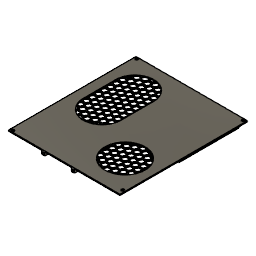
top-cover (Autodesk Fusion 360 design; units mm, degrees)
Autodesk Fusion 360 part; units mm, degrees
sketch "Sketch1" plane through (0, 0, 0) normal (0, 0, 1) x (1, 0, 0)
  line L0 (111, -154) -> (-111, -154)
  line L1 (-111, 100) -> (111, 100)
  circle A0 centre (106, -143.5) radius 1.95
  line L2 (-109, -154) -> (-103, -154)
  line L3 (-103, 100) -> (-109, 100)
  line L4 (109, -140) -> (103, -140)
  line L5 (-111, 100) -> (-111, -154)
  line L6 (-109, -147) -> (-109, 93)
  line L7 (111, 100) -> (111, -154)
  line L8 (-103, 93) -> (-103, 100)
  circle A1 centre (-106, -150.5) radius 1.95
  line L9 (103, 100) -> (103, 93)
  line L10 (-103, -147) -> (-109, -147)
  line L11 (-111, -154) -> (-109, -154)
  line L12 (103, -154) -> (111, -154)
  line L13 (-109, -154) -> (-109, -147)
  line L14 (111, 100) -> (103, 100)
  line L15 (-109, 93) -> (-103, 93)
  circle A2 centre (106, -143.5) radius 1.95
  circle A3 centre (-106, -150.5) radius 1.95
  circle A4 centre (106, 96.5) radius 1.95
  line L16 (103, -140) -> (103, -154)
  line L17 (-109, 100) -> (-109, 93)
  line L18 (-109, 100) -> (-111, 100)
  circle A5 centre (-106, 96.5) radius 1.95
  line L19 (103, 93) -> (109, 93)
  line L20 (111, -154) -> (111, 100)
  line L21 (-111, -154) -> (-111, 100)
  line L22 (109, 93) -> (109, -140)
  circle A6 centre (-106, 96.5) radius 1.95
  circle A7 centre (106, 96.5) radius 1.95
  line L23 (-103, -154) -> (-103, -147)
  line L24 (-109, -147) -> (-109, -154)
  line L25 (-109, 93) -> (-109, 100)
  circle A8 centre (-106, 96.5) radius 2.725
  circle A9 centre (106, 96.5) radius 2.725
  circle A10 centre (106, -143.5) radius 2.725
  circle A11 centre (-106, -150.5) radius 2.725
  line L26 (-109, 84.9738) -> (-107, 84.9738)
  line L27 (-107, 84.9738) -> (-107, -35.0262)
  line L28 (-107, -35.0262) -> (-109, -35.0262)
  line L29 (-109, -35.0262) -> (-109, 84.9738)
  line L30 (109, 84.9738) -> (107, 84.9738)
  line L31 (107, 84.9738) -> (107, -35.0262)
  line L32 (107, -35.0262) -> (109, -35.0262)
  line L33 (109, -35.0262) -> (109, 84.9738)
  point P0 (0, 100)
  dimension "d3" = 5.45
  dimension "d4" = 5.45
  dimension "d5" = 5.45
  dimension "d6" = 5.45
  dimension "d11" = 2
  dimension "d12" = 120
  dimension "d13" = 222
  dimension "d14" = 254
  dimension "d15" = 2
  dimension "d16" = 120
  constraint horizontal L1
  constraint vertical L7
  constraint horizontal L0
  constraint vertical L21
  constraint coincident L0.start L7.end
  constraint coincident L1.start L5.start
  constraint concentric A1 A3
  constraint concentric A4 A7
  constraint concentric A6 A8
  constraint concentric A7 A9
  constraint concentric A2 A10
  constraint concentric A1 A11
  constraint horizontal L26
  constraint vertical L27
  constraint horizontal L28
  constraint vertical L29
  constraint coincident L6 L26.start
  constraint vertical L20
  constraint vertical L22
  constraint vertical L6
  constraint vertical L16
  constraint horizontal L4
  constraint horizontal L10
  constraint vertical L23
  constraint horizontal L19
  constraint vertical L9
  constraint horizontal L15
  constraint vertical L8
  constraint horizontal L30
  constraint vertical L31
  constraint horizontal L32
  constraint vertical L33
  constraint coincident L22 L30.start
  constraint collinear L26 L30
  measures "d3" diameter of A8
  measures "d4" diameter of A9
  measures "d5" diameter of A10
  measures "d6" diameter of A11
  measures "d11" distance of L26.start L26.end
  measures "d12" distance of L26.start L28.end
  measures "d13" distance of L1.end L1.start
  measures "d14" distance of L1.end L0.start
  measures "d15" distance of L30.start L30.end
  measures "d16" distance of L30.start L32.end
extrude "Extrude1" add sketch "Sketch1" along normal blind 2 contours L0 L1 L4 L7 L9 L12 L14 L16 L19 L20 L22 L33 | L0 L1 L4 L6 L8 L9 L10 L15 L16 L19 L22 L23 L26 L27 L28 L30 L31 L32 | L0 L2 L10 L13 L23 L24 | L0 L1 L5 L6 L11 L13 L17 L18 L21 L24 L25 L29 | L1 L3 L8 L15 L17 L25 | L22 L30 L31 L32 L33 | L6 L26 L27 L28 L29 makes body 1
extrude "Extrude2" add sketch "Sketch1" along normal blind 1 contours A8 | A9 | A10 | A11 bodies 1
extrude "Extrude3" add sketch "Sketch1" against normal blind 4 contours L22 L30 L31 L32 L33 | L6 L26 L27 L28 L29 bodies 1
sketch "Sketch2" plane through (0, -154, 0) normal (0, -1, 0) x (1, 0, 0)
  line L0 (-111, 0) -> (111, 0)
  line L1 (111, 0) -> (111, 2)
  line L2 (111, 2) -> (-111, 2)
  line L3 (-111, 2) -> (-111, 0)
  line L4 (-111, 2) -> (-86, 2)
  line L5 (-86, 2) -> (-86, 0)
  line L6 (-86, 0) -> (-111, 0)
  line L7 (-111, 0) -> (-111, 2)
  line L8 (111, 2) -> (86, 2)
  line L9 (86, 2) -> (86, 0)
  line L10 (86, 0) -> (111, 0)
  line L11 (111, 0) -> (111, 2)
  line L12 (-86, 2) -> (86, 2)
  line L13 (86, 2) -> (86, 0)
  line L14 (86, 0) -> (-86, 0)
  line L15 (-86, 0) -> (-86, 2)
  dimension "d19" = 25
  dimension "d20" = 25
  constraint horizontal L4
  constraint vertical L5
  constraint horizontal L6
  constraint vertical L7
  constraint coincident L2.end L3.start
  constraint horizontal L8
  constraint vertical L9
  constraint horizontal L10
  constraint vertical L11
  constraint coincident L1.end L2.start
  constraint horizontal L12
  constraint vertical L13
  constraint horizontal L14
  constraint vertical L15
  measures "d19" distance of L2.end L4.end
  measures "d20" distance of L1.end L8.end
fillet "Fillet3" radius 0.5 4 edges at (104.182, -142.7948, 1) (104.182, 97.2052, 1) (-107.818, 97.2052, 1) (-107.818, -149.7949, 1) on bodies 1
sketch "Sketch3" plane through (0, 0, 0) normal (0, 0, -1) x (1, 0, 0)
  line L0 (109, -84.9738) -> (107, -84.9738)
  line L1 (107, -84.9738) -> (107, 35.0262)
  line L2 (107, 35.0262) -> (109, 35.0262)
  line L3 (109, 35.0262) -> (109, -84.9738)
  line L4 (-107, 35.0262) -> (-107, -84.9738)
  line L5 (-107, -84.9738) -> (-109, -84.9738)
  line L6 (-109, -84.9738) -> (-109, 35.0262)
  line L7 (-109, 35.0262) -> (-107, 35.0262)
  circle A0 centre (-106, 150.5) radius 1.95
  circle A1 centre (-106, -96.5) radius 1.95
  circle A2 centre (106, 143.5) radius 1.95
  circle A3 centre (106, -96.5) radius 1.95
  line L8 (111, 154) -> (-111, 154)
  line L9 (-111, 154) -> (-111, -100)
  line L10 (-111, -100) -> (111, -100)
  line L11 (111, -100) -> (111, 154)
  line L12 (-111, 154) -> (-44.9, 154)
  line L13 (-44.9, 154) -> (-38.9, 154)
  line L14 (-38.9, 154) -> (-38.9, 145)
  line L15 (-38.9, 145) -> (-44.9, 145)
  line L16 (-44.9, 145) -> (-44.9, 154)
  line L17 (14.1, 154) -> (20.1, 154)
  line L18 (20.1, 154) -> (20.1, 145)
  line L19 (20.1, 145) -> (14.1, 145)
  line L20 (14.1, 145) -> (14.1, 154)
  dimension "d27" = 66.1
  dimension "d29" = 6
  dimension "d30" = 9
  dimension "d33" = 6
  dimension "d34" = 9
  dimension "d35" = 53
  constraint coincident L8.end L9.start
  constraint perpendicular L9 L12
  constraint horizontal L13
  constraint vertical L14
  constraint horizontal L15
  constraint vertical L16
  constraint horizontal L17
  constraint vertical L18
  constraint horizontal L19
  constraint vertical L20
  constraint collinear L13 L17
  constraint coincident L12.end L13.start
  measures "d27" distance of L8.end L12.end
  measures "d29" distance of L12.end L13.end
  measures "d30" distance of L12.end L15.end
  measures "d33" distance of L17.start L17.end
  measures "d34" distance of L17.start L19.end
  measures "d35" distance of L14 L20
extrude "Extrude5" add sketch "Sketch3" along normal blind 7 contours L8 L17 L18 L19 L20 | L8 L13 L14 L15 L16 bodies 1
sketch "Sketch4" plane through (0, -154, 0) normal (0, -1, 0) x (1, 0, 0)
  line L0 (-111, 0) -> (-44.9, 0)
  line L1 (-44.9, 0) -> (-44.9, -7)
  line L2 (-44.9, -7) -> (-38.9, -7)
  line L3 (-38.9, -7) -> (-38.9, 0)
  circle A0 centre (-41.9, -4) radius 1.95
  circle A1 centre (17.1, -4) radius 1.95
  line L4 (14.1, 0) -> (14.1, -7)
  line L5 (20.1, -7) -> (14.1, -7)
  line L6 (-38.9, 0) -> (14.1, 0)
  line L7 (14.1, 0) -> (14.1, -7)
  line L8 (14.1, -7) -> (20.1, -7)
  line L9 (20.1, -7) -> (20.1, 0)
  line L10 (20.1, 0) -> (111, 0)
  line L11 (111, 0) -> (111, 2)
  line L12 (111, 2) -> (-111, 2)
  line L13 (-111, 2) -> (-111, 0)
  line L14 (-38.9, 0) -> (-44.9, 0)
  line L15 (20.1, 0) -> (14.1, 0)
  dimension "d36" = 3.9
  dimension "d37" = 3.9
  dimension "d43" = 3
  dimension "d44" = 3
  dimension "d47" = 4
  dimension "d48" = 4
  measures "d36" diameter of A0
  measures "d37" diameter of A1
  measures "d43" distance of A1.centre L4
  measures "d44" distance of L1 A0.centre
  measures "d47" distance of A0.centre L14
  measures "d48" distance of A1.centre L15
extrude "Extrude6" cut sketch "Sketch4" against normal blind 8 contours A0 | A1 bodies 1
fillet "Fillet4" radius 0.4 2 edges at (-43.718, -154, -3.2948) (15.282, -154, -3.2948) on bodies 1
sketch "Sketch5" plane through (0, 0, 2) normal (0, 0, 1) x (-1, 0, 0)
  line L0 (111, 154) -> (-111, 154)
  line L1 (-111, 154) -> (-111, -100)
  line L2 (-111, -100) -> (111, -100)
  line L3 (111, -100) -> (111, 154)
  circle A0 centre (-54, 87) radius 40
  circle A1 centre (106, 150.5) radius 2.725
  circle A2 centre (-106, -96.5) radius 2.725
  circle A3 centre (106, -96.5) radius 2.725
  circle A4 centre (-106, 143.5) radius 2.725
  line L4 (16, 25) -> (16, -40)
  arc A5 (16, -40) -> (91, -40) centre (53.5, -40) ccw
  line L5 (91, -40) -> (91, 25)
  arc A6 (91, 25) -> (16, 25) centre (53.5, 25) ccw
  line L6 (53.5, 25) -> (53.5, -40) construction
  line L7 (53.5, 62.5) -> (111, 62.5)
  line L8 (53.5, -77.5) -> (111, -77.5)
  dimension "d63" = 80
  dimension "d69" = 65
  dimension "d70" = 75
  dimension "d72" = 67
  dimension "d73" = 57
  dimension "d74" = 60
  dimension "d75" = 20
  constraint tangent L4 A5
  constraint tangent A5 L5
  constraint parallel L4 L5
  constraint tangent L5 A6
  constraint tangent L4 A6
  constraint vertical L6
  constraint midpoint A6 L7.start
  constraint coincident L3 L7.end
  constraint tangent A6 L7
  constraint perpendicular L3 L7
  constraint midpoint A5 L8.start
  constraint coincident L3 L8.end
  constraint tangent A5 L8
  constraint perpendicular L3 L8
  measures "d63" diameter of A0
  measures "d69" distance of A6.centre A5.centre
  measures "d70" distance of L4 L5
  measures "d72" distance of L0 A0.centre
  measures "d73" distance of L1 A0.centre
  measures "d74" distance of L2 A5.centre
  measures "d75" distance of L3 L5
extrude "Extrude7" cut sketch "Sketch5" against normal blind 5 contours L4 A5 L5 A6 | A0 bodies 1
extrude "Extrude8" add sketch "Sketch5" against normal blind 2 separate body contours L4 A5 L5 A6 | A0 makes body 2 at (-41, 18.3333, 0) makes body 3 at (53.0036, -98.5272, 2)
sketch "Sketch6" plane through (0, 0, 2) normal (0, 0, 1) x (-1, 0, 0)
  line L0 (47.7265, -5) -> (50.6132, -10)
  line L1 (50.6132, -10) -> (56.3868, -10)
  line L2 (56.3868, -10) -> (59.2735, -5)
  line L3 (59.2735, -5) -> (56.3868, 0)
  line L4 (56.3868, 0) -> (50.6132, 0)
  line L5 (50.6132, 0) -> (47.7265, -5)
  line L6 (53.5, -5) -> (49.1699, -7.5) construction
  line L7 (53.5, -5) -> (53.5, -10) construction
  circle A0 centre (-54, 87) radius 40
  line L8 (-59.7735, 87) -> (-56.8868, 82)
  line L9 (-56.8868, 82) -> (-51.1132, 82)
  line L10 (-51.1132, 82) -> (-48.2265, 87)
  line L11 (-48.2265, 87) -> (-51.1132, 92)
  line L12 (-51.1132, 92) -> (-56.8868, 92)
  line L13 (-56.8868, 92) -> (-59.7735, 87)
  arc A1 (91, 25) -> (16, 25) centre (53.5, 25) ccw
  line L14 (16, 25) -> (16, -40)
  arc A2 (16, -40) -> (91, -40) centre (53.5, -40) ccw
  line L15 (91, -40) -> (91, 25)
  circle A3 centre (-54, 87) radius 40
  line L16 (53.5, -40) -> (53.5, 25)
  point P0 (53.5, -5)
  point P1 (-54, 87)
  dimension "d56" = 5
  dimension "d66" = 5
  constraint horizontal L1
  constraint coincident P0 L6.start
  constraint midpoint L0 L6.end
  constraint midpoint L1 L7.end
  constraint coincident P1 A0.centre
  constraint horizontal L9
  constraint coincident A2.centre L16.start
  constraint coincident A1.centre L16.end
  measures "d56" distance of P0 L5
  measures "d66" distance of P1 L13
extrude "Extrude9" cut sketch "Sketch6" against normal blind 2 contours L0 L1 L4 L5 L16 | L1 L2 L3 L4 L16 | L8 L9 L10 L11 L12 L13 bodies 2 3
pattern_linear "R-Pattern1" count 25 spacing 12 along (0, 1, 0) both ways count 9 spacing 12 along (0.866025, 0.5, 0) both ways of "Extrude9"
sketch "Sketch7" plane through (0, 0, 0) normal (0, 0, -1) x (1, 0, 0)
  line L0 (-16, 25) -> (-16, -40)
  arc A0 (-91, -40) -> (-16, -40) centre (-53.5, -40) ccw
  line L1 (-91, -40) -> (-91, 25)
  arc A1 (-16, 25) -> (-91, 25) centre (-53.5, 25) ccw
  circle A2 centre (54, 87) radius 40
  line L2 (109, -84.9738) -> (107, -84.9738)
  line L3 (107, -84.9738) -> (107, 35.0262)
  line L4 (107, 35.0262) -> (109, 35.0262)
  line L5 (109, 35.0262) -> (109, -84.9738)
  line L6 (-107, 35.0262) -> (-107, -84.9738)
  line L7 (-107, -84.9738) -> (-109, -84.9738)
  line L8 (-109, -84.9738) -> (-109, 35.0262)
  line L9 (-109, 35.0262) -> (-107, 35.0262)
  circle A3 centre (-106, 150.5) radius 1.95
  circle A4 centre (-106, -96.5) radius 1.95
  circle A5 centre (106, 143.5) radius 1.95
  circle A6 centre (106, -96.5) radius 1.95
  line L10 (20.1, 154) -> (20.1, 145)
  line L11 (20.1, 145) -> (14.1, 145)
  line L12 (14.1, 145) -> (14.1, 154)
  line L13 (14.1, 154) -> (-38.9, 154)
  line L14 (-38.9, 154) -> (-38.9, 145)
  line L15 (-38.9, 145) -> (-44.9, 145)
  line L16 (-44.9, 145) -> (-44.9, 154)
  line L17 (-44.9, 154) -> (-111, 154)
  line L18 (-111, 154) -> (-111, -100)
  line L19 (-111, -100) -> (111, -100)
  line L20 (111, -100) -> (111, 154)
  line L21 (111, 154) -> (20.1, 154)
  line L22 (102.95, -100) -> (-102.95, -100)
  line L23 (-102.95, -100) -> (-102.95, -95)
  line L24 (-102.95, -95) -> (102.95, -95)
  line L25 (102.95, -95) -> (102.95, -100)
  dimension "d76" = 205.9
  dimension "d77" = 5
  dimension "d78" = 8.05
  dimension "d79" = 8.05
  constraint horizontal L22
  constraint vertical L23
  constraint horizontal L24
  constraint vertical L25
  constraint collinear L19 L22
  measures "d76" distance of L22.start L22.end
  measures "d77" distance of L22.start L24.end
  measures "d78" distance of L20 L25
  measures "d79" distance of L18 L23
extrude "Extrude11" add sketch "Sketch7" along normal blind 5 contours L19 L22 L23 L24 L25 bodies 1
equation "d3 = d6"
equation "d4 = d6"
equation "d5 = d6"
equation "d27 = 82.1 mm - 16 mm"
equation "d34 = d30"
